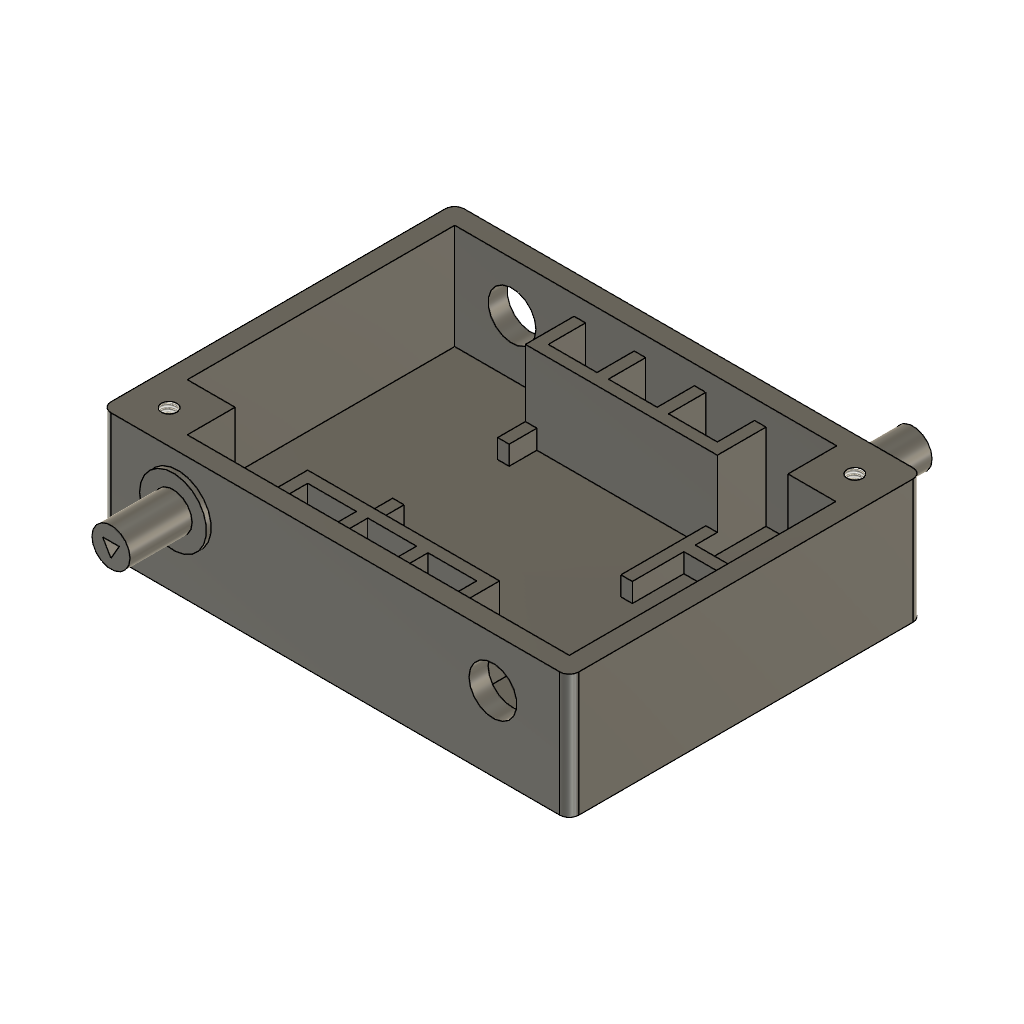
CasePart1 (Autodesk Fusion 360 design; units mm, degrees)
part number: 2026-10-03-18-17-18-057
Autodesk Fusion 360 part; units mm, degrees
sketch "Szkic1" plane through (0, 0, 0) normal (0, 0, 1) x (1, 0, 0)
  line L0 (0, 0) -> (49, 0)
  line L1 (49, 0) -> (49, 37)
  line L2 (49, 37) -> (0, 37)
  line L3 (0, 37) -> (0, 0)
  constraint horizontal L0
  constraint vertical L1
  constraint horizontal L2
  constraint vertical L3
  constraint coincident L0.start L3.end
extrude "Wyciągnięcie proste1" add sketch "Szkic1" along normal blind 2
sketch "Szkic2" plane through (0, 0, 2) normal (0, 0, 1) x (-1, 0, 0)
  line L0 (0, -37) -> (0, 0)
  line L1 (0, 0) -> (-49, 0)
  line L2 (-49, 0) -> (-49, -37)
  line L3 (-49, -37) -> (0, -37)
  line L4 (0, -37) -> (-2, -37)
  line L5 (-2, 0) -> (0, 0)
  line L6 (0, 0) -> (0, -37)
  line L7 (-14.5, -2) -> (-47, -2)
  line L8 (-49, -2) -> (-49, 0)
  line L9 (-49, 0) -> (-2, 0)
  line L10 (-49, -2) -> (-49, -37)
  line L11 (-49, -37) -> (-47, -37)
  line L12 (-47, -29.9) -> (-47, -2)
  line L13 (-2, -37) -> (-47, -37)
  line L14 (-34.5, -35) -> (-2, -35)
  line L15 (-2, -35) -> (-2, -7.1)
  line L16 (-47, -29.9) -> (-42, -29.9)
  line L17 (-34.5, -29.9) -> (-34.5, -30)
  line L18 (-7, -2) -> (-7, -7)
  line L19 (-7, -7) -> (-2, -7)
  line L20 (-2, -7) -> (-2, -7.1)
  line L21 (-14.5, -2) -> (-7, -2)
  line L22 (-42, -35) -> (-42, -29.9)
  line L23 (-42, -35) -> (-34.5, -35)
  constraint horizontal L4
  constraint vertical L15
  constraint horizontal L5
  constraint vertical L6
  constraint coincident L1 L5.start
  constraint coincident L0.start L3.end
  constraint horizontal L7
  constraint vertical L8
  constraint horizontal L9
  constraint coincident L1.end L2.start
  constraint vertical L10
  constraint horizontal L11
  constraint vertical L12
  constraint coincident L2.end L3.start
  constraint horizontal L13
  constraint horizontal L14
  constraint horizontal L16
  constraint vertical L17
  constraint perpendicular L18 L19
  constraint parallel L1 L21
  constraint perpendicular L16 L22
extrude "Wyciągnięcie proste2" add sketch "Szkic2" along normal blind 11
sketch "Szkic3" plane through (0, 0, 2) normal (0, 0, 1) x (-1, 0, 0)
  line L0 (-2, -35) -> (-2, -7.1)
  line L1 (-14.5, -2) -> (-47, -2)
  line L2 (-47, -2) -> (-47, -29.9)
  line L3 (-42, -35) -> (-2, -35)
  line L4 (-10, -10.6) -> (-2, -10.6)
  line L5 (-14.5, -27) -> (-14.5, -35)
  line L6 (-10, -10.6) -> (-14.5, -10.6)
  line L7 (-14.5, -10.6) -> (-14.5, -16)
  line L8 (-14.5, -9.4) -> (-14.5, -2)
  line L9 (-13.8092, -9.4) -> (-14.5, -9.4)
  line L10 (-13.8092, -9.4) -> (-2, -9.4)
  line L11 (-15.7, -35) -> (-15.7, -31.1)
  line L12 (-20, -31.1) -> (-15.7, -31.1)
  line L13 (-20, -29.9) -> (-15.7, -29.9)
  line L14 (-15.7, -27) -> (-15.7, -29.9)
  line L15 (-15.7, -31.1) -> (-15.7, -35)
  line L16 (-20, -29.9) -> (-33.4, -29.9)
  line L17 (-34.5, -29.9) -> (-42, -29.9)
  line L18 (-34.6, -33.7358) -> (-34.6, -35)
  line L19 (-34.6, -35) -> (-33.4, -35)
  line L20 (-33.4, -35) -> (-33.4, -31.1)
  line L21 (-34.6, -33.7358) -> (-34.6, -31.1)
  line L22 (-34.6, -31.1) -> (-34.6, -29.9)
  line L23 (-47, -27.6) -> (-47, -26.4)
  line L24 (-47, -29.9) -> (-47, -27.6)
  line L25 (-47, -27.6) -> (-47, -26.4)
  line L26 (-43.1782, -26.4) -> (-47, -26.4)
  line L27 (-47, -27.6) -> (-42.2525, -27.6)
  line L28 (-42.2525, -26.4) -> (-43.1782, -26.4)
  line L29 (-33.4, -2) -> (-34.6, -2)
  line L30 (-34.6, -27.6) -> (-42.2525, -27.6)
  line L31 (-42.2525, -26.4) -> (-34.6, -26.4)
  line L32 (-20, -31.1) -> (-33.4, -31.1)
  line L33 (-34.6, -30.1881) -> (-34.6, -27.6)
  line L34 (-18.5, -5.9) -> (-15.7, -5.9)
  line L35 (-20, -7.1) -> (-15.7, -7.1)
  line L36 (-20, -7.1) -> (-33.4, -7.1)
  line L37 (-18.5, -5.9) -> (-33.4, -5.9)
  line L38 (-15.7, -16) -> (-15.7, -7.1)
  line L39 (-15.7, -5.9) -> (-15.7, -2)
  line L40 (-33.4, -5.9) -> (-33.4, -2)
  line L41 (-14.5, -2) -> (-15.7, -2)
  line L42 (-33.4, -21) -> (-34.6, -21)
  line L43 (-33.4, -10) -> (-34.6, -10)
  line L44 (-33.4, -2) -> (-33.4, -5.9)
  line L45 (-33.4, -7.1) -> (-33.4, -10)
  line L46 (-33.4, -35) -> (-33.4, -31.1)
  line L47 (-33.4, -29.9) -> (-33.4, -21)
  line L48 (-15.7, -16) -> (-14.5, -16)
  line L49 (-15.7, -2) -> (-15.7, -5.9)
  line L50 (-15.7, -7.1) -> (-15.7, -16)
  line L51 (-14.5, -35) -> (-14.5, -27)
  line L52 (-14.5, -35) -> (-14.5, -27)
  line L53 (-15.7, -27) -> (-14.5, -27)
  line L54 (-34.6, -26.4) -> (-34.6, -21)
  line L55 (-34.6, -10) -> (-34.6, -2)
  line L56 (-33.4, -29.9) -> (-33.4, -21)
  line L57 (-33.4, -10) -> (-33.4, -7.1)
  line L58 (-47, -29.9) -> (-42, -29.9)
  line L59 (-42, -29.9) -> (-42, -35)
  line L60 (-2, -7.1) -> (-2, -7)
  line L61 (-2, -7) -> (-7, -7)
  line L62 (-7, -7) -> (-7, -2)
  line L63 (-7, -2) -> (-14.5, -2)
  line L64 (-15.7, -29.9) -> (-14.5, -29.9)
  line L65 (-34.6, -29.9) -> (-33.4, -29.9)
  line L66 (-15.7, -7.1) -> (-14.5, -7.1)
  line L67 (-33.4, -7.1) -> (-34.6, -7.1)
  constraint coincident L0 L4.end
  constraint perpendicular L0 L4
  constraint coincident L3 L5.end
  constraint perpendicular L3 L5
  constraint coincident L3 L11.start
  constraint perpendicular L3 L15
  constraint coincident L1 L39.end
  constraint perpendicular L1 L39
  constraint coincident L1 L8.end
  constraint perpendicular L1 L8
  constraint perpendicular L8 L9
  constraint coincident L0 L10.end
  constraint perpendicular L0 L10
  constraint perpendicular L11 L12
  constraint perpendicular L13 L14
  constraint collinear L14 L15
  constraint coincident L3 L18.end
  constraint perpendicular L3 L18
  constraint coincident L3 L19.end
  constraint perpendicular L20 L32
  constraint perpendicular L16 L22
  constraint coincident L2 L23.start
  constraint coincident L2 L23.end
  constraint coincident L2.end L24.start
  constraint perpendicular L25 L26
  constraint perpendicular L23 L27
  constraint coincident L1 L29.start
  constraint perpendicular L1 L40
  constraint coincident L22 L33.start
  constraint coincident L1 L29.end
  constraint perpendicular L1 L55
  constraint perpendicular L31 L54
  constraint collinear L33 L54
  constraint perpendicular L34 L39
  constraint perpendicular L35 L38
  constraint perpendicular L36 L57
  constraint perpendicular L37 L40
  constraint collinear L38 L39
  constraint collinear L40 L57
  constraint perpendicular L3 L46
  constraint perpendicular L42 L56
  constraint perpendicular L43 L55
  constraint collinear L44 L45
  constraint collinear L46 L47
  constraint perpendicular L7 L48
  constraint collinear L49 L50
  constraint perpendicular L5 L53
  constraint collinear L54 L55
  constraint collinear L56 L57
  constraint coincident L51 L64.end
  constraint perpendicular L51 L64
  constraint perpendicular L56 L65
  constraint coincident L8 L66.end
  constraint perpendicular L8 L66
  constraint coincident L55 L67.end
  constraint perpendicular L55 L67
extrude "Wyciągnięcie proste3" add sketch "Szkic3" along normal blind 2 contours L0 L4 L6 L7 L8 L9 L10 L38 L48 L50 L66 | L3 L5 L11 L12 L13 L15 L16 L17 L18 L19 L20 L21 L22 L32 L33 L46 L51 L52 L64 L65 | L5 L14 L51 L52 L53 L64 | L1 L8 L29 L34 L35 L36 L37 L39 L40 L41 L44 L49 L55 L66 L67 | L2 L17 L23 L25 L26 L27 L28 L30 L31 L33 L42 L47 L54 L56 L65 | L43 L45 L55 L57 L67
sketch "Szkic4" plane through (0, 0, 4) normal (0, 0, 1) x (-1, 0, 0)
  line L0 (-15.7, -29.9) -> (-33.4, -29.9)
  line L1 (-33.4, -29.9) -> (-33.4, -21)
  line L2 (-33.4, -21) -> (-34.6, -21)
  line L3 (-34.6, -21) -> (-34.6, -26.4)
  line L4 (-34.6, -26.4) -> (-47, -26.4)
  line L5 (-47, -26.4) -> (-47, -27.6)
  line L6 (-47, -27.6) -> (-34.6, -27.6)
  line L7 (-34.6, -27.6) -> (-34.6, -35)
  line L8 (-34.6, -35) -> (-33.4, -35)
  line L9 (-33.4, -35) -> (-33.4, -31.1)
  line L10 (-33.4, -31.1) -> (-15.7, -31.1)
  line L11 (-15.7, -31.1) -> (-15.7, -35)
  line L12 (-15.7, -35) -> (-14.5, -35)
  line L13 (-14.5, -35) -> (-14.5, -27)
  line L14 (-14.5, -27) -> (-15.7, -27)
  line L15 (-15.7, -27) -> (-15.7, -29.9)
  line L16 (-14.5, -35) -> (-15.7, -35)
  line L17 (-15.7, -35) -> (-15.7, -31.1)
  line L18 (-15.7, -29.9) -> (-14.5, -29.9)
  line L19 (-14.5, -29.9) -> (-14.5, -35)
  line L20 (-15.7, -29.9) -> (-34.6, -29.9)
  line L21 (-34.6, -29.9) -> (-34.6, -31.1)
  line L22 (-33.4, -31.1) -> (-15.7, -31.1)
  line L23 (-33.4, -31.1) -> (-33.4, -35)
  line L24 (-33.4, -35) -> (-34.6, -35)
  line L25 (-34.6, -35) -> (-34.6, -31.1)
  line L26 (-15.7, -31.1) -> (-20, -31.1)
  line L27 (-33.4, -31.1) -> (-29, -31.1)
  line L28 (-33.4, -31.1) -> (-28.3, -31.1)
  line L29 (-28.3, -31.1) -> (-28.3, -35)
  line L30 (-28.3, -35) -> (-27.1, -35)
  line L31 (-27.1, -35) -> (-27.1, -31.1)
  line L32 (-27.1, -31.1) -> (-22, -31.1)
  line L33 (-22, -31.1) -> (-22, -35)
  line L34 (-22, -35) -> (-20.8, -35)
  line L35 (-20.8, -35) -> (-20.8, -31.1)
  dimension "d67" = 5.1
  dimension "d68" = 1.2
  dimension "d69" = 5.1
  dimension "d70" = 1.2
  constraint horizontal L16
  constraint vertical L17
  constraint horizontal L18
  constraint vertical L19
  constraint coincident L0.start L15.end
  constraint coincident L12.end L13.start
  constraint horizontal L20
  constraint vertical L21
  constraint horizontal L22
  constraint coincident L7 L21.end
  constraint vertical L23
  constraint horizontal L24
  constraint vertical L25
  constraint coincident L8.end L9.start
  constraint coincident L22 L26.end
  constraint coincident L9.end L10.start
  constraint coincident L22 L27.end
  constraint perpendicular L11 L28
  constraint perpendicular L28 L29
  constraint perpendicular L29 L30
  constraint coincident L22 L31.end
  constraint perpendicular L22 L31
  constraint perpendicular L31 L32
  constraint perpendicular L10 L33
  constraint perpendicular L33 L34
  constraint coincident L22 L35.end
  constraint perpendicular L22 L35
  measures "d67" distance of L9.end L28.end
  measures "d68" distance of L29.end L30.end
  measures "d69" distance of L31.end L32.end
  measures "d70" distance of L33.end L34.end
extrude "Wyciągnięcie proste4" add sketch "Szkic4" along normal blind 7 contours L0 L7 L8 L9 L10 L11 L12 L13 L16 L17 L18 L19 L20 L21 L22 L23 L24 L25 L26 L27 L28 L32 | L10 L22 L33 L34 L35 | L10 L22 L29 L30 L31
sketch "Szkic5" plane through (0, 0, 4) normal (0, 0, 1) x (-1, 0, 0)
  line L0 (-34.6, -10) -> (-33.4, -10)
  line L1 (-33.4, -10) -> (-33.4, -7.1)
  line L2 (-33.4, -7.1) -> (-15.7, -7.1)
  line L3 (-15.7, -7.1) -> (-15.7, -16)
  line L4 (-15.7, -16) -> (-14.5, -16)
  line L5 (-14.5, -16) -> (-14.5, -10.6)
  line L6 (-14.5, -10.6) -> (-2, -10.6)
  line L7 (-2, -10.6) -> (-2, -9.4)
  line L8 (-2, -9.4) -> (-14.5, -9.4)
  line L9 (-14.5, -9.4) -> (-14.5, -2)
  line L10 (-14.5, -2) -> (-15.7, -2)
  line L11 (-15.7, -2) -> (-15.7, -5.9)
  line L12 (-15.7, -5.9) -> (-33.4, -5.9)
  line L13 (-33.4, -5.9) -> (-33.4, -2)
  line L14 (-33.4, -2) -> (-34.6, -2)
  line L15 (-34.6, -2) -> (-34.6, -10)
  line L16 (-34.6, -2) -> (-33.4, -2)
  line L17 (-33.4, -2) -> (-33.4, -5.9)
  line L18 (-33.4, -7.1) -> (-34.6, -7.1)
  line L19 (-34.6, -7.1) -> (-34.6, -2)
  line L20 (-33.4, -7.1) -> (-14.5, -7.1)
  line L21 (-14.5, -7.1) -> (-14.5, -5.9)
  line L22 (-15.7, -5.9) -> (-15.7, -2)
  line L23 (-15.7, -2) -> (-14.5, -2)
  line L24 (-14.5, -2) -> (-14.5, -5.9)
  line L25 (-33.4, -5.9) -> (-28.3, -5.9)
  line L26 (-28.3, -5.9) -> (-28.3, -2)
  line L27 (-28.3, -2) -> (-27.1, -2)
  line L28 (-27.1, -2) -> (-27.1, -5.9)
  line L29 (-27.1, -5.9) -> (-22, -5.9)
  line L30 (-22, -5.9) -> (-22, -2)
  line L31 (-22, -2) -> (-20.8, -2)
  line L32 (-20.8, -2) -> (-20.8, -5.9)
  line L33 (-33.4, -5.9) -> (-28.3, -5.9)
  line L34 (-27.1, -5.9) -> (-22, -5.9)
  line L35 (-20.8, -5.9) -> (-15.7, -5.9)
  line L36 (-33.4, -7.1) -> (-14.5, -7.1)
  dimension "d71" = 5.1
  dimension "d72" = 1.2
  dimension "d73" = 5.1
  dimension "d74" = 1.2
  constraint horizontal L16
  constraint vertical L17
  constraint horizontal L18
  constraint vertical L19
  constraint coincident L1.end L2.start
  constraint coincident L14.end L15.start
  constraint horizontal L20
  constraint vertical L21
  constraint coincident L9 L21.end
  constraint vertical L22
  constraint horizontal L23
  constraint vertical L24
  constraint coincident L10.end L11.start
  constraint coincident L12.end L13.start
  constraint perpendicular L22 L35
  constraint perpendicular L13 L25
  constraint perpendicular L12 L26
  constraint perpendicular L26 L27
  constraint coincident L12 L28.end
  constraint perpendicular L12 L28
  constraint perpendicular L28 L29
  constraint perpendicular L12 L30
  constraint perpendicular L30 L31
  constraint coincident L12 L32.end
  constraint perpendicular L12 L32
  constraint collinear L33 L34
  constraint collinear L34 L35
  measures "d71" distance of L12.end L25.end
  measures "d72" distance of L26.end L27.end
  measures "d73" distance of L28.end L29.end
  measures "d74" distance of L30.end L31.end
extrude "Wyciągnięcie proste5" add sketch "Szkic5" along normal blind 7 contours L2 L9 L10 L11 L12 L13 L14 L15 L16 L17 L18 L19 L20 L21 L22 L23 L24 L25 L29 L33 L34 L35 L36 | L12 L26 L27 L28 | L12 L30 L31 L32
sketch "Szkic12" plane through (0, 0, 0) normal (0, -1, 0) x (1, 0, 0)
  line L0 (0, 0) -> (49, 0)
  line L1 (49, 0) -> (49, 13)
  line L2 (49, 13) -> (0, 13)
  line L3 (0, 13) -> (0, 0)
  line L4 (0, 0) -> (8, 0)
  line L5 (8, 0) -> (8, 7.8)
  circle A0 centre (8, 7.8) radius 2
  dimension "d27" = 8
  dimension "d28" = 7.8
  dimension "d62" = 4
  constraint coincident L0.start L3.end
  constraint perpendicular L3 L4
  constraint perpendicular L4 L5
  constraint coincident L5.end A0.centre
  measures "d27" distance of L0.start L4.end
  measures "d28" distance of L4.end L5.end
  measures "d62" diameter of A0
extrude "Wyciągnięcie proste8" add sketch "Szkic12" along normal blind 7 contours A0
sketch "Szkic13" plane through (0, 0, 0) normal (0, -1, 0) x (1, 0, 0)
  line L0 (0, 0) -> (49, 0)
  line L1 (49, 0) -> (49, 13)
  line L2 (49, 13) -> (0, 13)
  line L3 (0, 13) -> (0, 0)
  line L4 (49, 0) -> (41, 0)
  line L5 (41, 0) -> (41, 7.8)
  circle A0 centre (41, 7.8) radius 2.5
  circle A1 centre (8, 7.8) radius 2
  dimension "d54" = 8
  dimension "d55" = 7.8
  dimension "d56" = 5
  constraint coincident L0.end L1.start
  constraint perpendicular L1 L4
  constraint perpendicular L0 L5
  constraint coincident L5.end A0.centre
  measures "d54" distance of L0.end L4.end
  measures "d55" distance of L4.end L5.end
  measures "d56" diameter of A0
extrude "Wyciągnięcie proste9" cut sketch "Szkic13" against normal blind 2 contours A0
sketch "Szkic14" plane through (0, 37, 0) normal (0, 1, 0) x (-1, 0, 0)
  line L0 (-49, 0) -> (0, 0)
  line L1 (0, 0) -> (0, 13)
  line L2 (0, 13) -> (-49, 13)
  line L3 (-49, 13) -> (-49, 0)
  line L4 (-49, 0) -> (-41, 0)
  line L5 (-41, 0) -> (-41, 7.8)
  circle A0 centre (-41, 7.8) radius 2
  dimension "d57" = 8
  dimension "d58" = 7.8
  dimension "d61" = 4
  constraint coincident L0.start L3.end
  constraint perpendicular L3 L4
  constraint perpendicular L0 L5
  measures "d57" distance of L0.start L4.end
  measures "d58" distance of L4.end L5.end
  measures "d61" diameter of A0
extrude "Wyciągnięcie proste10" add sketch "Szkic14" along normal blind 7 contours A0
sketch "Szkic15" plane through (0, 37, 0) normal (0, 1, 0) x (-1, 0, 0)
  line L0 (-49, 0) -> (0, 0)
  line L1 (0, 0) -> (0, 13)
  line L2 (0, 13) -> (-49, 13)
  line L3 (-49, 13) -> (-49, 0)
  line L4 (0, 0) -> (-8, 0)
  line L5 (-8, 0) -> (-8, 7.8)
  circle A0 centre (-8, 7.8) radius 2.5
  circle A1 centre (-41, 7.8) radius 2
  dimension "d42" = 8
  dimension "d43" = 7.8
  dimension "d44" = 5
  constraint coincident L0.end L1.start
  constraint perpendicular L1 L4
  constraint perpendicular L4 L5
  constraint coincident L5.end A0.centre
  measures "d42" distance of L0.end L4.end
  measures "d43" distance of L4.end L5.end
  measures "d44" diameter of A0
extrude "Wyciągnięcie proste11" cut sketch "Szkic15" against normal blind 2 contours A0
sketch "Szkic16" plane through (0, 0, 13) normal (0, 0, 1) x (-1, 0, 0)
  line L0 (-42, -29.9) -> (-47, -29.9)
  line L1 (-47, -29.9) -> (-47, -2)
  line L2 (-14.5, -2) -> (-7, -2)
  line L3 (-7, -2) -> (-7, -7)
  line L4 (-7, -7) -> (-2, -7)
  line L5 (-2, -7) -> (-2, -7.1)
  line L6 (-2, -7.1) -> (-2, -35)
  line L7 (-2, -35) -> (-42, -35)
  line L8 (-42, -35) -> (-42, -29.9)
  line L9 (-49, 0) -> (-49, -37)
  line L10 (-49, -37) -> (0, -37)
  line L11 (0, -37) -> (0, 0)
  line L12 (0, 0) -> (-49, 0)
  line L13 (0, 0) -> (-3.5928, 0)
  line L14 (-3.5928, 0) -> (-3.5928, -3.5)
  line L15 (-3.5928, -3.5) -> (0, -3.5)
  line L16 (0, -3.5) -> (0, 0)
  line L17 (-49, -37) -> (-45.5, -37)
  line L18 (-45.5, -37) -> (-45.5, -33.4072)
  line L19 (-45.5, -33.4072) -> (-49, -33.4072)
  line L20 (-49, -33.4072) -> (-49, -37)
  line L21 (-47, -2) -> (-14.5, -2)
  constraint horizontal L13
  constraint vertical L14
  constraint horizontal L15
  constraint vertical L16
  constraint coincident L11.end L12.start
  constraint horizontal L17
  constraint vertical L18
  constraint horizontal L19
  constraint vertical L20
  constraint coincident L9.end L10.start
hole "Otwór1" at (45.5, 33.4072, 13) at (3.5928, 3.5, 13) direction (0, 0, -1) diameter 1.623 depth 8 tip angle 118
thread "Gwint1" "ISO Metric profile 2.0 M2x0.4 M2x0.4 6H" major diameter 2.074 minor diameter 1.623 pitch 0.4 angle 60 resizes the face on face at (44.6888, 33.4275, 10.3333) on face at (3.6736, 2.6925, 10.3333)
fillet "Zaokrąglenie1" radius 1 4 edges at (0, 0, 6.5) (49, 0, 6.5) (0, 37, 6.5) (49, 37, 6.5)
sketch "Szkic17" plane through (0, 44, 0) normal (0, 1, 0) x (-1, 0, 0)
  circle A0 centre (-41, 7.8) radius 2
  circle A1 centre (-41, 7.8) radius 2
  circle A2 centre (-41, 7.8) radius 1
  line L0 (-41, 6.8) -> (-40.1339, 8.2998)
  line L1 (-41, 6.8) -> (-41.8661, 8.2998)
  line L2 (-41.8661, 8.2998) -> (-40.1339, 8.2998)
  constraint concentric A0 A1
  constraint concentric A1 A2
  constraint coincident A2 L0.start
  constraint coincident A2 L0.end
  constraint coincident A2 L1.end
  constraint horizontal L2
extrude "Wyciągnięcie proste12" cut sketch "Szkic17" against normal blind 3 contours L0 L1 L2
sketch "Szkic18" plane through (0, -7, 0) normal (0, -1, 0) x (1, 0, 0)
  circle A0 centre (8, 7.8) radius 2
  circle A1 centre (8, 7.8) radius 2
  circle A2 centre (8, 7.8) radius 1
  line L0 (8, 6.8) -> (8.8661, 8.2999)
  line L1 (8, 6.8) -> (7.1339, 8.2999)
  line L2 (7.1339, 8.2999) -> (8.8661, 8.2999)
  dimension "d77" = 2
  constraint concentric A0 A1
  constraint concentric A1 A2
  constraint coincident A2 L0.start
  constraint coincident A2 L0.end
  constraint coincident A2 L1.end
  constraint horizontal L2
  measures "d77" diameter of A2
extrude "Wyciągnięcie proste13" cut sketch "Szkic18" against normal blind 3 contours L0 L1 L2
sketch "Szkic19" plane through (0, 0, 0) normal (0, -1, 0) x (1, 0, 0)
  circle A0 centre (8, 7.8) radius 2
  circle A1 centre (41, 7.8) radius 2.5
  line L0 (48, 0) -> (48, 13)
  line L1 (48, 13) -> (1, 13)
  line L2 (1, 13) -> (1, 0)
  line L3 (1, 0) -> (48, 0)
  circle A2 centre (8, 7.8) radius 3.5
  dimension "d80" = 7
  constraint concentric A0 A2
  measures "d80" diameter of A2
extrude "Wyciągnięcie proste14" add sketch "Szkic19" along normal blind 0.5 contours A2
sketch "Szkic20" plane through (0, 37, 0) normal (0, 1, 0) x (-1, 0, 0)
  circle A0 centre (-8, 7.8) radius 2.5
  circle A1 centre (-41, 7.8) radius 2
  line L0 (-48, 13) -> (-48, 0)
  line L1 (-48, 0) -> (-1, 0)
  line L2 (-1, 0) -> (-1, 13)
  line L3 (-1, 13) -> (-48, 13)
  circle A2 centre (-41, 7.8) radius 3.5
  dimension "d83" = 7
  constraint concentric A1 A2
  measures "d83" diameter of A2
extrude "Wyciągnięcie proste15" add sketch "Szkic20" along normal blind 0.5 contours A2
